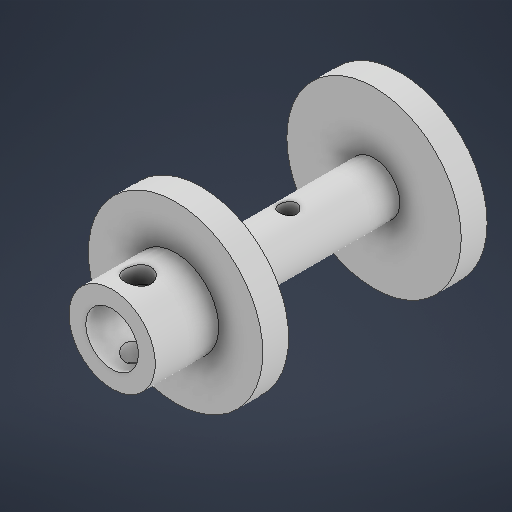
# Autodesk Inventor part: 1_1_8_bobine_cable
Saved by Autodesk Inventor 2026 (Build 300175000, 175)
## iProperties
Created: 2025-05-11
Part Number: 1_1_8_bobine_cable
Material: Generic
Document SubType Name: Modeling
Designer: remg9
Density: 1 g/cm^3
Appearance: Default
Author: remg9
Autodesk Inventor part; units mm, degrees
ref_plane "YZ Plane" through (0, 0, 0) normal (1, 0, 0) x (0, 1, 0)
ref_plane "XZ Plane" through (0, 0, 0) normal (0, 1, 0) x (-1, 0, 0)
ref_plane "XY Plane" through (0, 0, 0) normal (0, 0, 1) x (1, 0, 0)
sketch "Sketch1" plane through (0, 0, 0) normal (1, 0, 0) x (0, 1, 0)
  line L0 (0, 9.2763) -> (0, -19.0767)
  line L1 (0, -19.0767) -> (10.1045, -19.0767)
  line L2 (10.1045, -19.0767) -> (10.1045, -16.0767)
  line L3 (10.1045, -16.0767) -> (3, -16.0767)
  line L4 (3, -16.0767) -> (3, 3.9233)
  line L5 (3, 3.9233) -> (10.1045, 3.9233)
  line L6 (10.1045, 3.9233) -> (10.1045, 6.9233)
  line L7 (10.1045, 6.9233) -> (5, 6.9233)
  line L8 (5, 6.9233) -> (5, 14.2763)
  line L9 (5, 14.2763) -> (3.05, 14.2763)
  line L10 (3.05, 14.2763) -> (3.05, 9.2763)
  line L11 (3.05, 9.2763) -> (0, 9.2763)
  point P0 (0, 0)
  dimension "d0" = 20
  dimension "d1" = 3
  dimension "d2" = 3
  dimension "d3" = 3
  dimension "d4" = 5
  dimension "d5" = 3.05
  dimension "d6" = 5
  constraints: 24 end point, 9 perpendicular, 2 point on line, 2 vertical
  measures "d0" distance of L3.end L4.end
  measures "d1" distance between parallel lines of L0 L4
  measures "d2" distance between parallel lines of L1 L3
  measures "d3" distance between parallel lines of L7 L5
  measures "d4" distance between parallel lines of L0 L8
  measures "d5" distance of L10.end L0.start
  measures "d6" distance of L9.end L10.end
revolve "Revolution1" add sketch "Sketch1" angle 360 about axis through (0, 0, 9.2763) along (0, 0, -1)
sketch "Sketch2" plane through (0, 0, 0) normal (0, 1, 0) x (-1, 0, 0)
  circle A0 centre (0, 11.2763) radius 1.5
  line L0 (-5, 14.2763) -> (5, 14.2763) projected
  circle A1 centre (0, -6.0767) radius 1
  line L1 (-10.1045, 3.9233) -> (10.1045, 3.9233) projected
  point P0 (0, 0)
  dimension "d8" = 3
  dimension "d11" = 3
  dimension "d12" = 10
  dimension "d13" = 2
  constraints: 2 centre point
  measures "d8" diameter of A0
  measures "d11" distance from line of L0 A0.centre
  measures "d12" distance from line of L1 A1.centre
  measures "d13" diameter of A1
extrude "Extrusion1" cut sketch "Sketch2" along normal through all both and the other way through all
body "Solid1"
